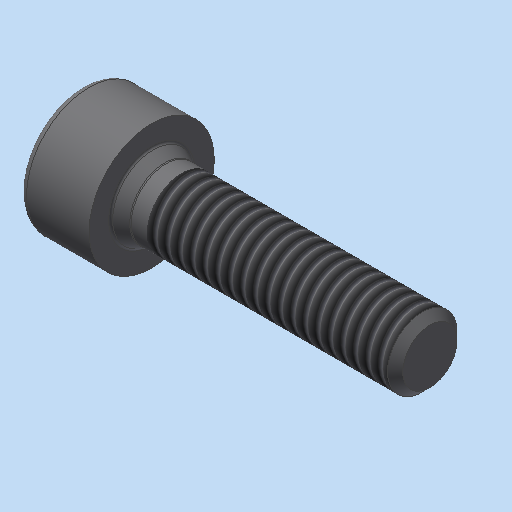
# Autodesk Inventor part: Zylinderschraube_ISO_4762___M2_5x10_A2-70
Saved by Autodesk Inventor 2023.3 (Build 273359000, 359)
## iProperties
Shininess: 64.0
Length Units: 11269
Angle Units: 11279
Time Units: 11290
Mass Units: 11283
Length Display Precision: 3
Angle Display Precision: 2
Compacted: True
Part Number: Zylinderschraube_ISO_4762___M2_5x10_A2-70
Document SubType Name: Modeling
Created: 2004-04-03
Material: xStahl_AnP_Dummymaterial
Description: =<RBPARTNOTITLE2>
Vendor: NORM8
Designer: S.Riedelsheimer
Manufacturer: Standard
Standards Organization: Custom
Density: 7.85 g/cm^3
Mass: 0.647738 g
Surface Area: 1.52973 cm^2
Volume: 0.0825143 cm^3
Appearance: Stahl - normal AnP
Density: 0.0
Volumn: 0.0
Area: 0.0
PropertySet Name: Model Information
Control State: 0
Master: False
Checked Out: False
CNS_NB: Zylinderschraube ISO 4762 - M2.5x10
CNS_NN: ISO 4762
CNS_NT: Zylinderschrauben mit Innensechskant
CNS_NBSYN: Zylinderschraube ISO 4762 - $NENN.
CNS_LINA: Zylinderschraube ISO 4762 - M2.5x10
CNS_D: 2.500
CNS_D3: 1.948
CNS_P: 0.450
CNS_L: 10.000
CNS_S: 2.000
CNS_HM: 10.000
CNS_DK: 4.500
CNS_DA: 3.100
CNS_DS: 2.500
CNS_E: 2.300
CNS_K: 2.500
CNS_R: 0.100
CNS_T: 1.100
CNS_V: 0.250
CNS_DW: 4.180
CNS_W: 0.850
CNS_LF: 0.510
CNS_LG: 1.350
CNS_FORM: 1.000
CNS_NENN: M2.5x10
CNS_KT: DUMMY
PSOL_IDENT_0: {C:\partsolutions8\data\23d-libs\bosch_bamberg\schrauben\zylinderschrauben\din_en_iso_4762.prj},172
PSOL_IDENT_1: {M=Nenngewinde},{VTYP=3D},{NB=Zylinderschraube ISO 4762 - M2.5x10},{NN=ISO 4762},{DATE=26.11.2003},{
PSOL_IDENT_2: GEOMDATE=26.11.2003},{VERSION=v2},{LINEID=230},{LINESUBID=-1},{WBVAR=}  {NB=Zylinderschraube ISO 476
PSOL_IDENT_3: 2 - M2.5x10},{LINA=Zylinderschraube ISO 4762 - M2.5x10},{KT=DUMMY},{IDNR=},{D=2.500},{D3=1.948},{P=0
PSOL_IDENT_4: .450},{L=10.000},{S=2.000},{HM=10.000},{DK=4.500},{DA=3.100},{DS=2.500},{E=2.300},{K=2.500},{R=0.100
PSOL_IDENT_5: },{T=1.100},{V=0.250},{DW=4.180},{W=0.850},{LF=0.510},{LG=1.350},{FORM=1.000},{NENN=M2.5x10}
RBPARTNOTITLE2: Zylinderschrauben mit Innensechskant
RBPARTNOTITLE1: Hexagon socket head cap screws
AnP_Kategorie: 4
RBDRAWINGMISSINGSPEC: --
RBPARTMADEOF: ISO 4762 - M2,5x10 - A2-70
Title: Zylinderschraube ISO 4762 - M2.5x10
Author: S.Riedelsheimer
Keywords: =<RBPARTMADEOF>
Comments: =<RBSURFACE2>
Revision Number: 01
Autodesk Inventor part; units mm, degrees
sketch "Skizze_2" plane through (0, 0, 0) normal (0, 0, 1) x (1, 0, 0)
  line L0 (13, 0) -> (-5.5, 0)
  line L1 (-0.2726, 0) -> (-0.85, 1)
  line L2 (-0.85, 1) -> (-2.35, 1)
  line L3 (-2.35, 1) -> (-2.5, 1.15)
  line L4 (-2.5, 1.15) -> (-2.5, 2)
  arc A0 (-2.25, 2.25) -> (-2.5, 2) centre (-2.25, 2) ccw
  line L5 (-2.25, 2.25) -> (0, 2.25)
  line L6 (0, 2.25) -> (0, 1.55)
  arc A1 (0, 1.55) -> (0.0562, 1.4601) centre (0.1, 1.55) ccw
  line L7 (0.0562, 1.4601) -> (0.4662, 1.2601)
  arc A2 (0.4662, 1.2601) -> (0.51, 1.25) centre (0.51, 1.35) ccw
  line L8 (0.51, 1.25) -> (9.724, 1.25)
  line L9 (9.724, 1.25) -> (10, 0.974)
  line L10 (10, 0.974) -> (10, 0)
  line L11 (10, 0) -> (-0.2726, 0)
  constraints: 24 end point, 6 point on circle, 3 centre point
revolve "Drehung1" add sketch "Skizze_2" angle 360 about axis through (13, 0, 0) along (1, 0, 0)
thread "Gewinde1" size "M2.5x0.45" class "6g" standard "ANSI Metric M Profile" length 8.65
sketch "Skizze_1" plane through (-0.85, 0, 0) normal (1, 0, 0) x (0, 0, -1)
  line L0 (-1, 0.5774) -> (-1, -0.5774)
  line L1 (-1, -0.5774) -> (0, -1.1547)
  line L2 (0, -1.1547) -> (1, -0.5774)
  line L3 (1, -0.5774) -> (1, 0.5774)
  line L4 (1, 0.5774) -> (0, 1.1547)
  line L5 (0, 1.1547) -> (-1, 0.5774)
  constraints: 12 end point
extrude "Extrusion1" cut sketch "Skizze_1" against normal blind 2.2
ref_plane "IP1_XY" through (0, 0, 0) normal (1, 0, 0) x (0, 0, -1)
ref_plane "IP1_YZ" through (0, 0, 0) normal (0, 0, -1) x (0, 1, 0)
ref_plane "IP3_XY" through (10, 0, 0) normal (1, 0, 0) x (0, 0, -1)
ref_plane "IP3_YZ" through (10, 0, 0) normal (0, 0, -1) x (0, 1, 0)
ref_plane "IP2_XY" through (-2.5, 0, 0) normal (1, 0, 0) x (0, 0, -1)
ref_plane "IP2_YZ" through (-2.5, 0, 0) normal (0, 0, -1) x (0, 1, 0)
